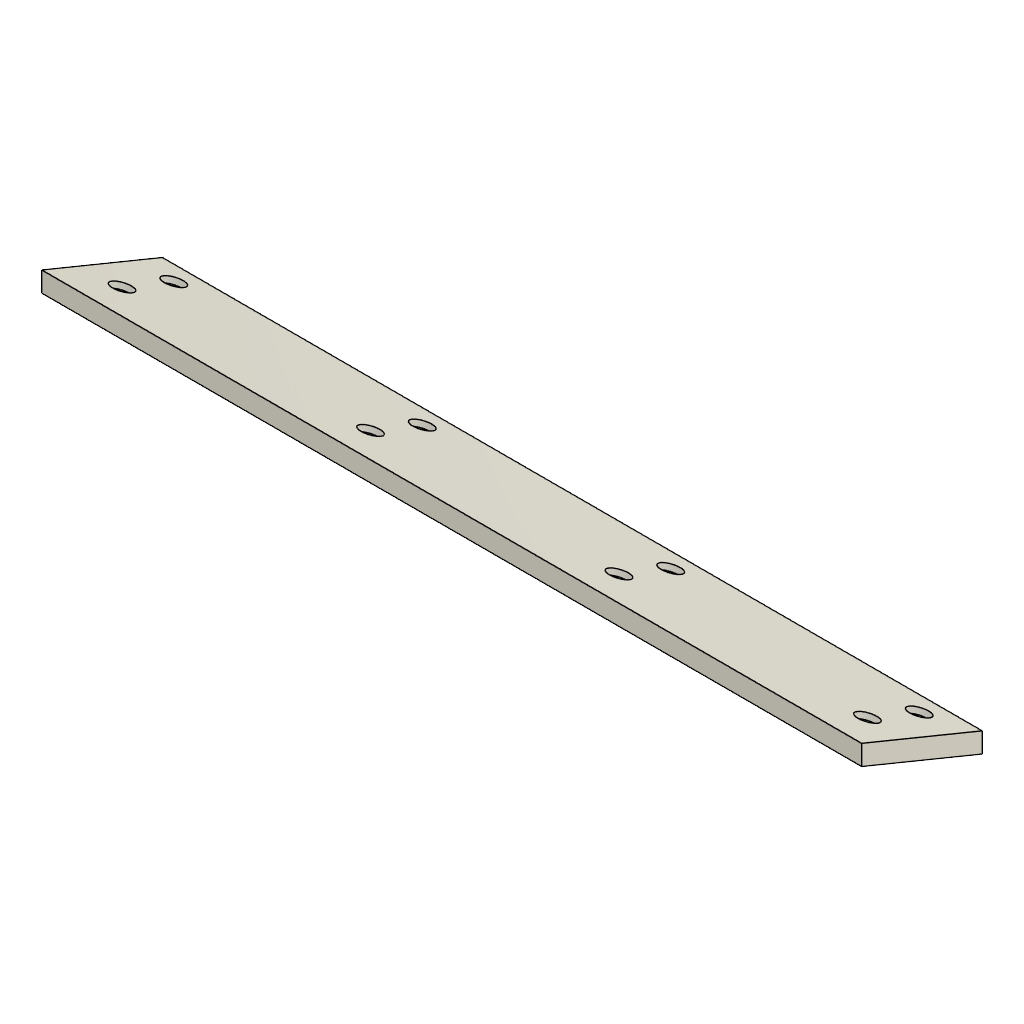
name_sign_LEDs (Autodesk Fusion 360 archive; units mm, degrees)
design "Name Sign LED Holder Bottom"
part number: 2026-10-25-14-42-28-917
Autodesk Fusion 360 part; units mm, degrees
sketch "Name sign LED holder bottom" plane through (0, 0, 0) normal (1, 0, 0) x (0, 1, 0)
  line L0 (0, 18.6852) -> (0, 13.281)
  line L1 (0, 13.281) -> (32.3823, 0)
  line L2 (32.3823, 0) -> (32.3823, 5.4042)
  line L3 (32.3823, 5.4042) -> (0, 18.6852)
  point P0 (0, 13.281)
  dimension "d1" = 5
  dimension "d2" = 112.3
  dimension "d3" = 35
  dimension "d4" = 5.4042
  dimension "d5" = 5.4042
  constraint vertical L0
  constraint parallel L1 L3
  constraint parallel L0 L2
  constraint coincident P0 L0.end
  measures "d1" distance of L1 L3
  measures "d2" angle of L0 L3
  measures "d3" distance of P0 L1.end
  measures "d4" distance of L0.start P0
  measures "d5" distance of L1.end L2.end
extrude "Extrude1" add sketch "Name sign LED holder bottom" along normal blind 220
sketch "Magnet holes" plane through (0, 6.5599, 15.9948) normal (0, 0.379456, 0.92521) x (-1, 0, 0)
  line L0 (0, -27.9098) -> (0, 7.0902)
  line L1 (0, 7.0902) -> (-220, 7.0902)
  line L2 (-220, 7.0902) -> (-220, -27.9098)
  line L3 (-220, -27.9098) -> (0, -27.9098)
  circle A0 centre (-210, -20.4098) radius 2.75
  dimension "d17" = 5.5
  dimension "d18" = 10
  dimension "d19" = 7.5
  measures "d17" diameter of A0
  measures "d18" distance of L2 A0.centre
  measures "d19" distance of L3 A0.centre
extrude "Extrude2" cut sketch "Magnet holes" against normal blind 1.5 contours A0
pattern_linear "R-Pattern1" count 4 spacing 66.6667 along (-1, 0, 0) count 2 spacing 15 along (0, -0.92521, 0.379456) of "Extrude2"
equation "magnet_hole_diameter = 5.5 mm"
equation "magnet_hole_depth = 1.5 mm"
equation "number_of_magnet_columns = 4"
equation "number_of_magnet_rows = 2"
equation "magnet_hole_side_offset = 10 mm"
equation "magnet_hole_top_offset = 7.5 mm"
equation "magnet_pattern_length = 220.00 mm - 2 * ( magnet_hole_side_offset )"
equation "d17 = magnet_hole_diameter"
equation "d18 = magnet_hole_side_offset"
equation "d19 = magnet_hole_top_offset"
equation "d20 = -magnet_hole_depth"
equation "d22 = number_of_magnet_columns"
equation "d23 = number_of_magnet_rows"
equation "d24 = magnet_pattern_length"
equation "d25 = magnet_pattern_height"
equation "vertical_part_width = 5.00 mm"
equation "magnet_pattern_height = 35.00 mm - vertical_part_width - 2 * ( magnet_hole_top_offset )"
named bodies: "Name sign LED holder bottom"

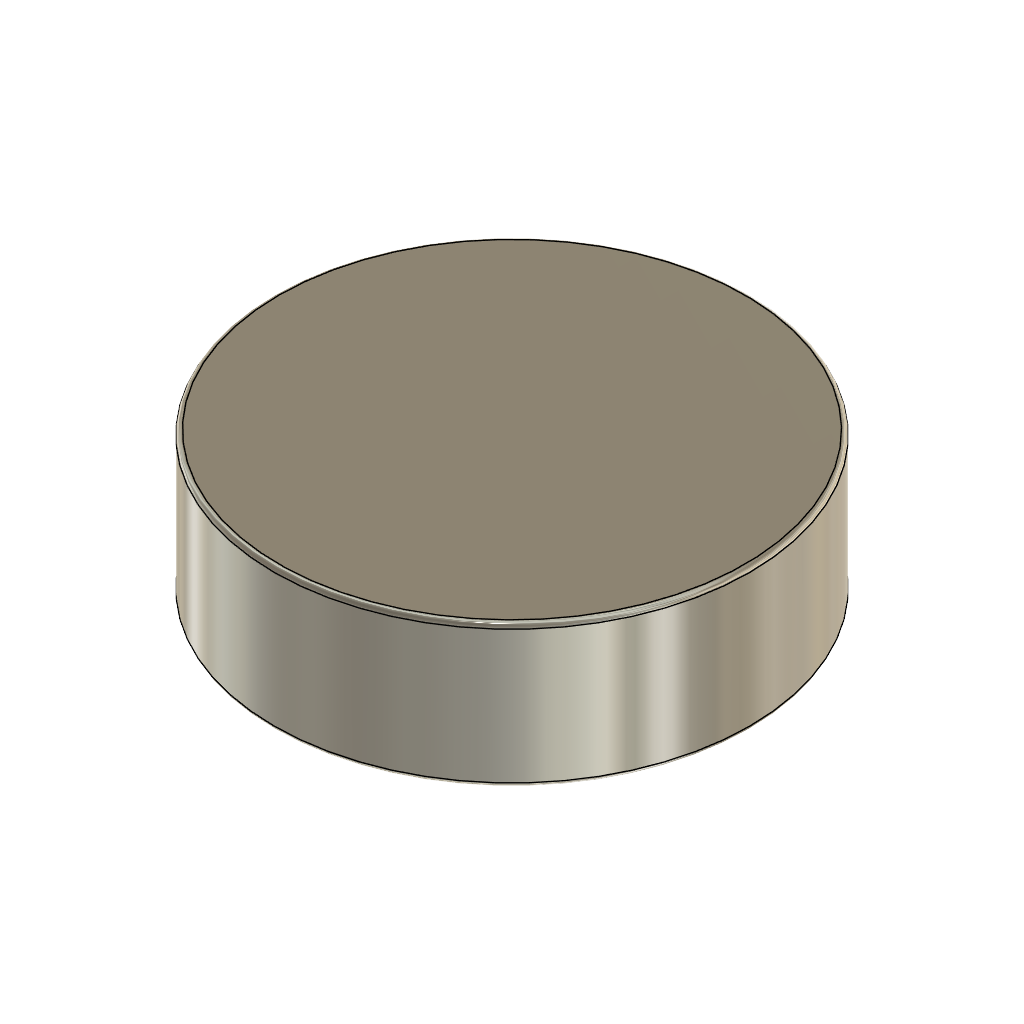
design "5 mm x 1.5 mm Neodymium Disc Magnet"
Autodesk Fusion 360 part; units mm, degrees
sketch "5 mm x 1.5 mm neodymium disc magnet" plane through (0, 0, 0) normal (0, 0, 1) x (1, 0, 0)
  circle A0 centre (0, 0) radius 2.5
  dimension "d1" = 5
  constraint coincident A0.centre origin
  measures "d1" diameter of A0
extrude "Extrude1" add sketch "5 mm x 1.5 mm neodymium disc magnet" along normal blind 1.5
fillet "Fillet1" radius 0.05 2 edges at (-2.3308, -0.904, 1.5) (-2.3308, -0.904, 0)
named bodies: "5 mm x 1.5 mm Neodymium Disc Magnet"

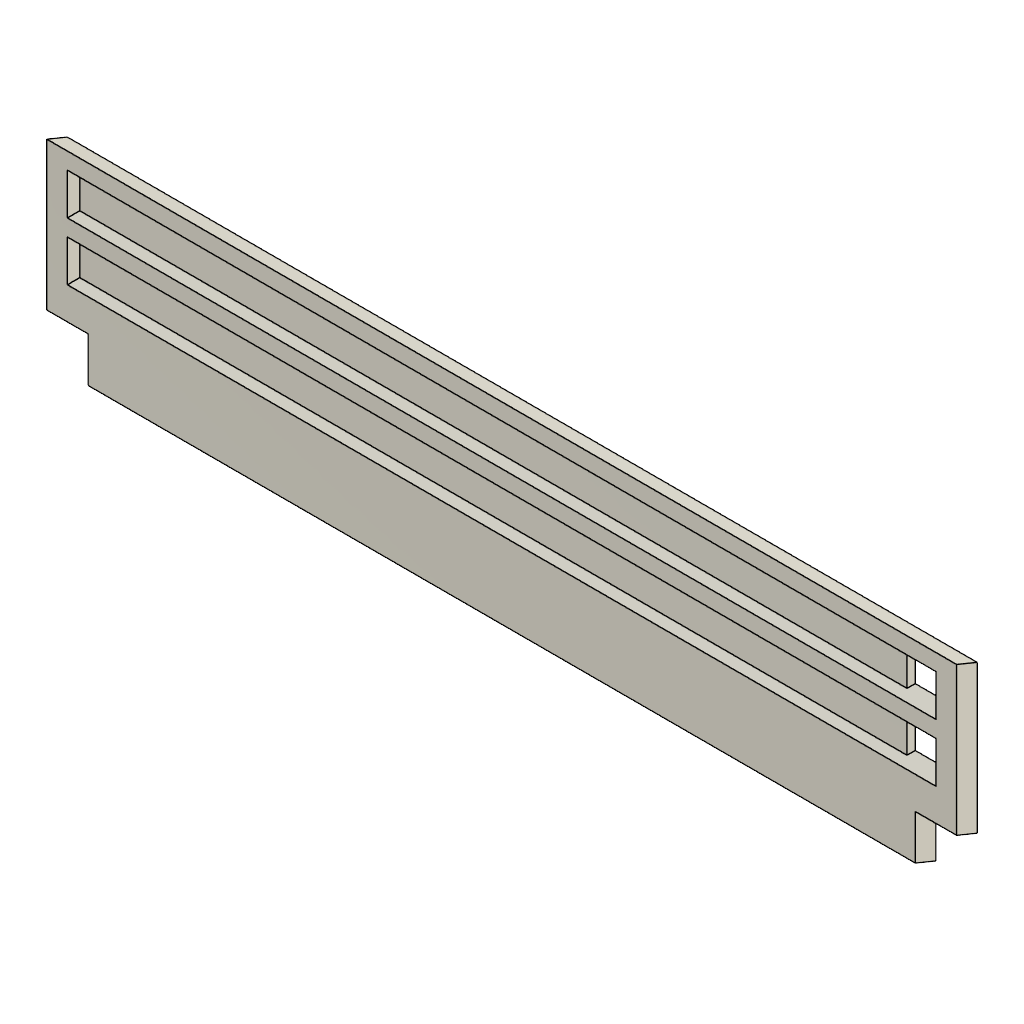
design "Name Sign LED Holder Top Front"
part number: 2026-10-25-15-26-22-685
Autodesk Fusion 360 part; units mm, degrees
sketch "Name sign LED holder top front" plane through (0, 0, 0) normal (1, 0, 0) x (0, 1, 0)
  line L0 (5, 46.5964) -> (5, 0.0004)
  line L1 (5, 0.0004) -> (0, 2.051)
  line L2 (0, 2.051) -> (0, 48.647)
  line L3 (0, 48.647) -> (5, 46.5964)
  dimension "d2" = 46.596
  dimension "d3" = 112.3
  dimension "d26" = 112.3
  dimension "d27" = 5
  constraint parallel L0 L2
  measures "d2" distance of L2.end L1.end
  measures "d3" angle of L1 L2
  measures "d26" angle of L2 L3
  measures "d27" distance of L0 L2
extrude "Extrude1" add sketch "Name sign LED holder top front" along normal blind 220
sketch "LED grooves" plane through (0, 0, 0) normal (0, -1, 0) x (1, 0, 0)
  line L0 (0, 48.647) -> (0, 2.051)
  line L1 (0, 2.051) -> (220, 2.051)
  line L2 (220, 2.051) -> (220, 48.647)
  line L3 (5, 44.647) -> (215, 44.647)
  line L4 (215, 44.647) -> (215, 34.647)
  line L5 (215, 34.647) -> (5, 34.647)
  line L6 (5, 34.647) -> (5, 44.647)
  line L7 (5, 30.647) -> (215, 30.647)
  line L8 (215, 30.647) -> (215, 20.647)
  line L9 (215, 20.647) -> (5, 20.647)
  line L10 (5, 20.647) -> (5, 30.647)
  line L11 (215, 44.647) -> (205, 44.647)
  line L12 (205, 44.647) -> (205, 34.647)
  line L13 (205, 34.647) -> (215, 34.647)
  line L14 (215, 34.647) -> (215, 44.647)
  line L15 (215, 30.647) -> (205, 30.647)
  line L16 (205, 30.647) -> (205, 20.647)
  line L17 (205, 20.647) -> (215, 20.647)
  line L18 (215, 20.647) -> (215, 30.647)
  line L19 (220, 48.647) -> (0, 48.647)
  dimension "d8" = 5
  dimension "d9" = 210
  dimension "d10" = 5
  dimension "d11" = 10
  dimension "d12" = 10
  dimension "d14" = 4
  dimension "d15" = 10
  dimension "d28" = 4
  constraint horizontal L3
  constraint vertical L4
  constraint horizontal L5
  constraint vertical L6
  constraint horizontal L7
  constraint vertical L8
  constraint horizontal L9
  constraint vertical L10
  constraint collinear L6 L10
  constraint collinear L4 L8
  constraint horizontal L11
  constraint vertical L12
  constraint horizontal L13
  constraint vertical L14
  constraint coincident L5 L12.end
  constraint horizontal L15
  constraint vertical L16
  constraint horizontal L17
  constraint vertical L18
  constraint coincident L9 L16.end
  constraint collinear L12 L16
  measures "d8" distance of L0 L6
  measures "d9" distance of L3.start L3.end
  measures "d10" distance of L2 L4
  measures "d11" distance of L3.start L5.end
  measures "d12" distance of L7.start L9.end
  measures "d14" distance of L5 L7
  measures "d15" distance of L12 L14
  measures "d28" distance of L3 L19
extrude "Extrude2" cut sketch "LED grooves" against normal blind 3 contours L3 L5 L6 L12 | L7 L9 L10 L16
extrude "Extrude3" cut sketch "LED grooves" against normal blind 5 contours L3 L4 L5 L11 L12 L13 L14 | L7 L8 L9 L15 L16 L17 L18
sketch "Support" plane through (220, 0, 0) normal (1, 0, 0) x (0, 1, 0)
  line L0 (0, 2.051) -> (5, 0.0004)
  line L1 (5, 0.0004) -> (5, 46.5964)
  line L2 (0, 48.647) -> (0, 2.051)
  line L3 (0, 12.859) -> (5, 10.8084)
  line L4 (0, 12.859) -> (0, 2.051)
  line L5 (0, 2.051) -> (5, 0.0004)
  line L6 (5, 0.0004) -> (5, 10.8084)
  line L7 (5, 46.5964) -> (0, 48.647)
  dimension "d20" = 10.808
  constraint coincident L2 L3.start
  constraint coincident L1 L3.end
  constraint parallel L0 L3
  constraint coincident L0.start L2.end
  constraint coincident L0.end L1.start
  measures "d20" distance of L0.start L3.start
extrude "Extrude4" cut sketch "Support" against normal blind 10 contours L0 L1 L2 L3 L4 L5 L6
extrude "Extrude5" cut sketch "Support" against normal blind 10 from surface at -210 contours L0 L1 L2 L3 L4 L5 L6
named bodies: "Name sign LED holder top front"

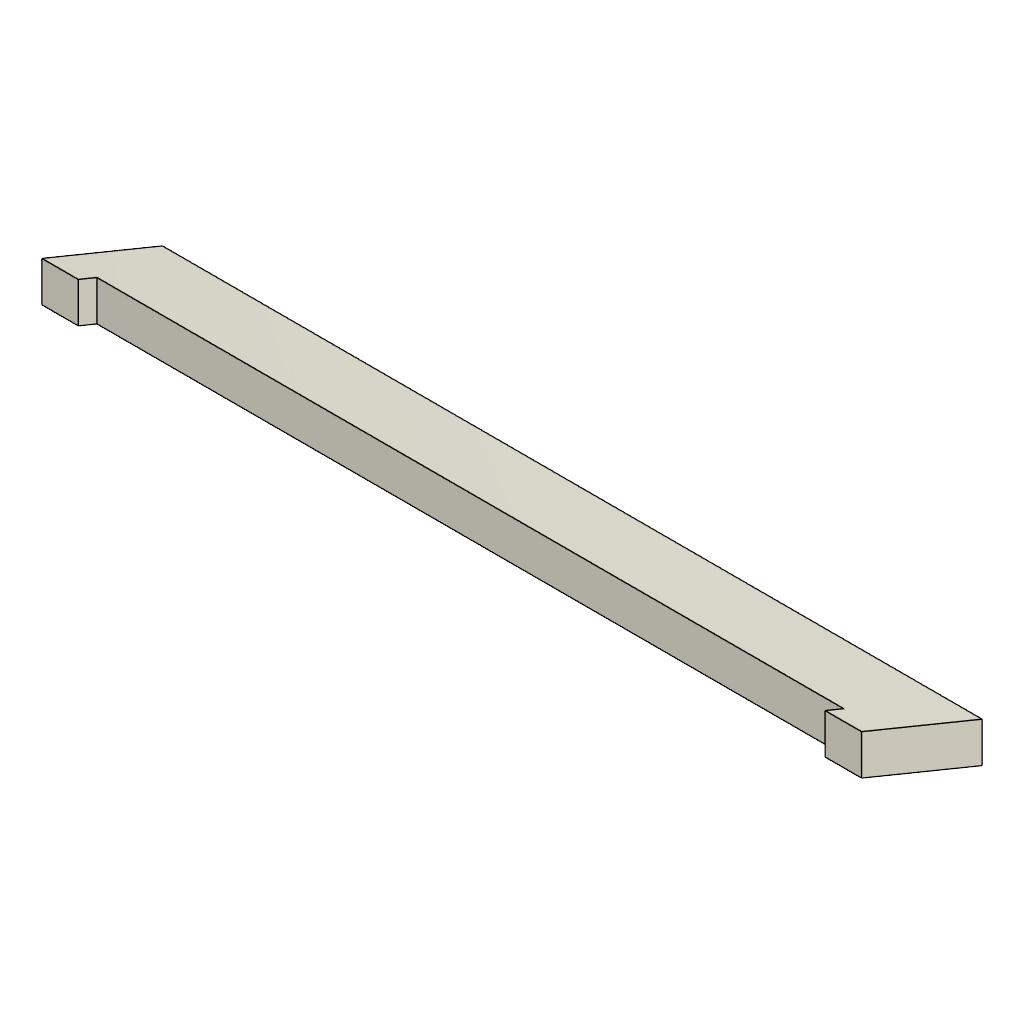
design "Name Sign LED Holder Top Back"
part number: 2026-10-25-17-00-14-466
Autodesk Fusion 360 part; units mm, degrees
sketch "Name sign LED holder top" plane through (0, 0, 0) normal (1, 0, 0) x (0, 1, 0)
  line L0 (0, 24.0894) -> (0, 13.281)
  line L1 (0, 13.281) -> (32.3823, 0)
  line L2 (32.3823, 0) -> (32.3823, 10.8084)
  line L3 (32.3823, 10.8084) -> (0, 24.0894)
  dimension "d1" = 35
  dimension "d2" = 10
  dimension "d3" = 112.3
  constraint vertical L0
  constraint parallel L0 L2
  constraint parallel L1 L3
  measures "d1" distance of L0.end L1.end
  measures "d2" distance of L1 L3
  measures "d3" angle of L0 L3
extrude "Extrude1" add sketch "Name sign LED holder top" along normal blind 220
sketch "Magnet holes" plane through (0, 4.6626, 11.3687) normal (0, -0.379456, -0.92521) x (1, 0, 0)
  line L0 (0, 5.0396) -> (0, -29.9604)
  line L1 (0, -29.9604) -> (220, -29.9604)
  line L2 (220, -29.9604) -> (220, 5.0396)
  line L3 (220, 5.0396) -> (0, 5.0396)
  circle A0 centre (10, -7.4604) radius 2.75
  dimension "d19" = 5.5
  dimension "d20" = 12.5
  dimension "d21" = 10
  measures "d19" diameter of A0
  measures "d20" distance of L3 A0.centre
  measures "d21" distance of L0 A0.centre
extrude "Extrude2" cut sketch "Magnet holes" against normal blind 1.5 contours A0
pattern_linear "R-Pattern1" count 4 spacing 66.6667 along (1, 0, 0) count 2 spacing 15 along (0, 0.92521, -0.379456) of "Extrude2"
sketch "Supports" plane through (220, 0, 0) normal (1, 0, 0) x (0, 1, 0)
  line L0 (32.3823, 10.8084) -> (0, 24.0894)
  line L1 (0, 24.0894) -> (0, 13.281)
  line L2 (0, 13.281) -> (32.3823, 0)
  line L3 (32.3823, 0) -> (32.3823, 10.8084)
  line L4 (5, 22.0387) -> (5, 11.2304)
  line L5 (5, 22.0387) -> (0, 24.0894)
  line L6 (0, 24.0894) -> (0, 13.281)
  line L7 (0, 13.281) -> (5, 11.2304)
  dimension "d28" = 5
  constraint coincident L0 L4.start
  constraint coincident L2 L4.end
  constraint parallel L1 L4
  constraint coincident L0.end L1.start
  constraint coincident L1.end L2.start
  measures "d28" distance of L1 L4
extrude "Extrude3" cut sketch "Supports" against normal blind 200.4 from surface at -9.8 contours L0 L1 L2 L4 L5 L6 L7
equation "magnet_hole_diameter = 5.5 mm"
equation "magnet_hole_depth = 1.5 mm"
equation "number_of_magnet_columns = 4"
equation "number_of_magnet_rows = 2"
equation "magnet_hole_side_offset = 10 mm"
equation "magnet_hole_top_offset = 7.5 mm"
equation "magnet_pattern_length = 220.00 mm - 2 * ( magnet_hole_side_offset )"
equation "magnet_pattern_height = 35.00 mm - vertical_part_width - 2 * ( magnet_hole_top_offset )"
equation "vertical_part_width = 5.00 mm"
equation "support_width = 10 mm"
equation "support_clearance = 0.2 mm"
equation "d19 = magnet_hole_diameter"
equation "d20 = vertical_part_width + magnet_hole_top_offset"
equation "d21 = magnet_hole_side_offset"
equation "d22 = -magnet_hole_depth"
equation "d24 = number_of_magnet_columns"
equation "d25 = number_of_magnet_rows"
equation "d26 = magnet_pattern_length"
equation "d27 = magnet_pattern_height"
equation "d29 = -( support_width - support_clearance )"
equation "d30 = -( 220.00 mm - 2 * support_width + 2 * support_clearance )"
named bodies: "Name sign LED holder top"
